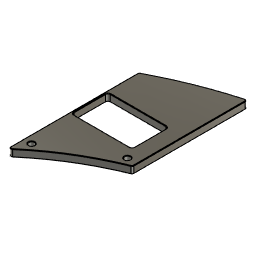
Oled Cover v3 (Autodesk Fusion 360 design; units mm, degrees)
Autodesk Fusion 360 part; units mm, degrees
sketch "Kyria Plate Case Guard - 6 columns - 0.1mm Kerf" plane through (0, 0, 0) normal (0, 0, 1) x (1, 0, 0)
  arc A0 (-87.7446, 61.8437) -> (-109.4199, 54.0197) centre (-45.433, -89.3111) ccw
  arc A1 (-118.6916, 49.5109) -> (-119.225, 48.6264) centre (-118.225, 48.6264) ccw
  arc A2 (-87.1007, 13.9039) -> (-117.5713, -4.5431) centre (-45.433, -89.3111) ccw
  circle A3 centre (-115.725, 1.4721) radius 1.2
  circle A4 centre (-90.725, 16.1859) radius 1.2
  line L0 (-119.225, 48.6264) -> (-119.225, -3.7943)
  arc A5 (-86.475, 60.8807) -> (-87.7446, 61.8437) centre (-87.475, 60.8807) ccw
  arc A6 (-109.4199, 54.0197) -> (-118.6916, 49.5109) centre (-45.3859, -89.4444) ccw
  line L1 (-86.475, 14.8313) -> (-86.475, 60.8807)
  arc A7 (-119.225, -3.7943) -> (-117.5713, -4.5431) centre (-118.225, -3.7864) ccw
  arc A8 (-87.1007, 13.9039) -> (-86.475, 14.8313) centre (-87.475, 14.8313) ccw
  line L2 (-118.225, 35.5859) -> (-93.225, 35.5859)
  line L3 (-93.225, 35.5859) -> (-93.225, 20.5859)
  line L4 (-93.225, 20.5859) -> (-118.225, 20.5859)
  line L5 (-118.225, 20.5859) -> (-118.225, 35.5859)
  arc A9 (-119.025, -3.7934) -> (-117.7015, -4.3913) centre (-118.225, -3.7864) ccw
  arc A10 (-87.1756, 14.0894) -> (-117.7015, -4.3913) centre (-45.433, -89.3111) ccw
  arc A11 (-87.1756, 14.0894) -> (-86.675, 14.8313) centre (-87.475, 14.8313) ccw
  line L6 (-86.675, 14.8313) -> (-86.675, 60.8807)
  arc A12 (-86.675, 60.8807) -> (-87.6906, 61.6511) centre (-87.475, 60.8807) ccw
  arc A13 (-87.6906, 61.6511) -> (-109.3384, 53.837) centre (-45.433, -89.3111) ccw
  arc A14 (-109.3384, 53.837) -> (-118.5983, 49.334) centre (-45.3859, -89.4444) ccw
  arc A15 (-118.5983, 49.334) -> (-119.025, 48.6264) centre (-118.225, 48.6264) ccw
  line L7 (-119.025, 48.6264) -> (-119.025, -3.7934)
  dimension "d1" = 25
  dimension "d2" = 15
  dimension "d3" = 4.4
  dimension "d4" = 1
  dimension "d10" = 0.2
  constraint coincident A2.end A7.end
  constraint horizontal L2
  constraint vertical L3
  constraint horizontal L4
  constraint vertical L5
  measures "d1" distance of L2.start L2.end
  measures "d2" distance of L2.start L4.end
  measures "d3" distance of A4.centre L4
  measures "d4" distance of L0 L5
extrude "Extrude1" add sketch "Kyria Plate Case Guard - 6 columns - 0.1mm Kerf" along normal blind 3 contours A9 A10 A11 L6 A12 A13 A14 A15 L7
fillet "Fillet1" radius 1 4 edges at (-118.225, 35.5859, 1.5) (-93.225, 35.5859, 1.5) (-93.225, 20.5859, 1.5) (-118.225, 20.5859, 1.5)
chamfer "Chamfer1" distance 0.2 angle 45 16 edges at (-103.1826, 6.0781, 3) (-86.8118, 14.3838, 3) (-86.675, 37.856, 3) (-86.9915, 61.5181, 3) (-98.6581, 58.1419, 3) (-114.0053, 51.6615, 3) (-118.9101, 49.0395, 3) (-119.025, 22.4165, 3) (-103.1826, 6.0781, 0) (-119.025, 22.4165, 0) (-118.9101, 49.0395, 0) (-114.0053, 51.6615, 0) (-98.6581, 58.1419, 0) (-86.9915, 61.5181, 0) (-86.675, 37.856, 0) (-86.8118, 14.3838, 0) 2 faces at (-107.9692, 41.1919, 0) (-107.9692, 41.1919, 3)
